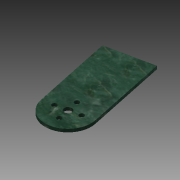
# Autodesk Inventor part: Pitch_Side
Saved by Autodesk Inventor 2013 (Build 170138000, 138)
## iProperties
Created: 2013-09-30
Part Number: Pitch_Side
Material: Generic
Document SubType Name: Modeling
Designer: Jeff
Density: 1 g/cm^3
Author: Jeff
Autodesk Inventor part; units mm, degrees
ref_plane "YZ Plane" through (0, 0, 0) normal (1, 0, 0) x (0, 1, 0)
ref_plane "XZ Plane" through (0, 0, 0) normal (0, 1, 0) x (-1, 0, 0)
ref_plane "XY Plane" through (0, 0, 0) normal (0, 0, 1) x (1, 0, 0)
ref_plane "Work Plane1" through (-3.1788, -1.377, 0) normal (0, 0, 1) x (0.9785, 0.2063, 0)
sketch "Sketch1" plane through (-3.1788, -1.377, 0) normal (0, 0, 1) x (0.9785, 0.2063, 0)
  line L0 (-1.6417, 1.1837) -> (22.3532, 0.6885) projected
  line L1 (-9.7043, -50.3859) -> (27.9877, -51.1639) projected
  line L2 (-2, 1.5875) -> (22, 1.5875)
  line L3 (22, 1.5875) -> (22, -40.1375)
  line L4 (10, -52.1375) -> (10, -52.1375)
  line L5 (-2, -40.1375) -> (-2, 1.5875)
  circle A0 centre (10, -40.1375) radius 2
  arc A1 (-2, -40.1375) -> (10, -52.1375) centre (10, -40.1375) ccw
  arc A2 (10, -52.1375) -> (22, -40.1375) centre (10, -40.1375) ccw
  circle A3 centre (10, -34.1375) radius 1.25
  circle A4 centre (4, -40.1375) radius 1.25
  circle A5 centre (10, -46.1375) radius 1.25
  circle A6 centre (16, -40.1375) radius 1.25
  line L6 (10, 1.5875) -> (10, -20.8493)
  point P0 (3.3945, 0.6917)
  dimension "d0" = 4
  dimension "d1" = 12
  dimension "d2" = 12
  dimension "d3" = 12
  dimension "d4" = 2.5
  dimension "d5" = 6
  dimension "d8" = 360
  dimension "d10" = 24
  constraints: 10 end point, 7 centre point, 4 point on circle, 4 tangent, 2 parallel, 1 horizontal, 1 perpendicular, 1 vertical, 10 other
  measures "d0" diameter of A0
  measures "d1" distance from line of L4 A0.centre
  measures "d2" radius of A1
  measures "d3" radius of A2
  measures "d4" diameter of A3
  measures "d5" distance of A0.centre A3.centre
  measures "d10" distance between parallel lines of L3 L5
extrude "Extrusion1" add sketch "Sketch1" along normal blind 1.5875
equation "\"d1\" = 0.5 * d10"
equation "\"d2\" = 0.5 * d10"
equation "\"d3\" = 0.5 * d10"
body "Solid1"
